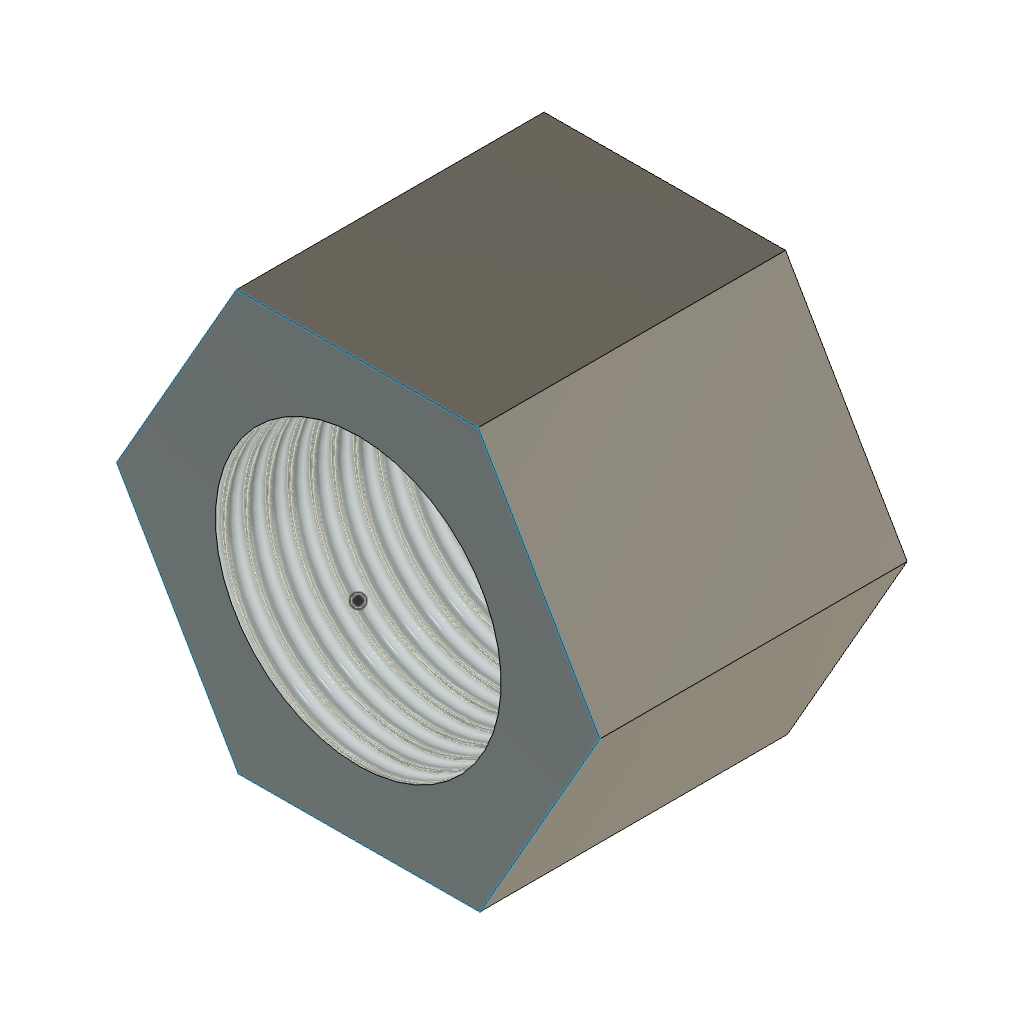
nut (Autodesk Fusion 360 design; units mm, degrees)
part number: 2026-10-08-14-31-20-378
Autodesk Fusion 360 part; units mm, degrees
sketch "Sketch1" plane through (0, 0, 0) normal (0, 1, 0) x (1, 0, 0)
  line L0 (11.0852, 19.0031) -> (-10.9146, 19.1016)
  line L1 (-10.9146, 19.1016) -> (-21.9998, 0.0985)
  line L2 (-21.9998, 0.0985) -> (-11.0852, -19.0031)
  line L3 (-11.0852, -19.0031) -> (10.9146, -19.1016)
  line L4 (10.9146, -19.1016) -> (21.9998, -0.0985)
  line L5 (21.9998, -0.0985) -> (11.0852, 19.0031)
  dimension "d1" = 22
  measures "d1" distance of L0.start origin
extrude "Extrude2" add sketch "Sketch1" along normal blind 28
hole "Hole2" at (0, 0, 0) direction (0, 1, 0) diameter 26.022 depth 125 tip angle 118
thread "Thread2" "ISO Metric profile 28.0 M28x2 M28x2 6H" thread offset 0 thread depth 7.4
